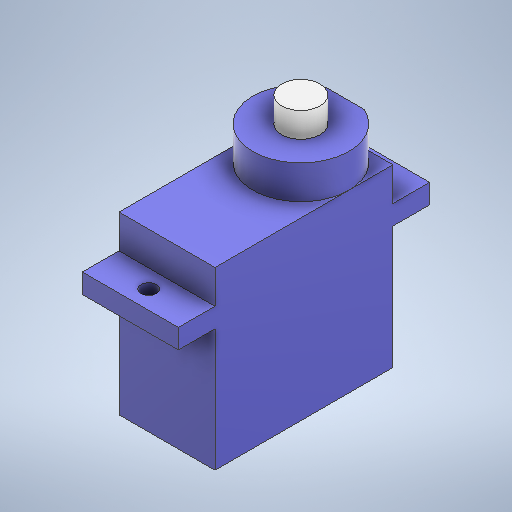
# Autodesk Inventor part: SG90
Saved by Autodesk Inventor 2025.3 (Build 293356030, 356C)
## iProperties
Created: 2025-10-27
Part Number: SG90
Material: 폴리스티렌
Document SubType Name: Modeling
Designer: work
Density: 1.021 g/cm^3
Appearance: 매끄러움 - 흰색
Author: work
Autodesk Inventor part; units mm, degrees
ref_plane "YZ Plane" through (0, 0, 0) normal (1, 0, 0) x (0, 1, 0)
ref_plane "XZ Plane" through (0, 0, 0) normal (0, 1, 0) x (-1, 0, 0)
sketch "스케치1" plane through (0, 0, 0) normal (0, 1, 0) x (-1, 0, 0)
  line L0 (0, 0) -> (12.3, 0)
  line L1 (12.3, 0) -> (12.3, -22.8)
  line L2 (12.3, -22.8) -> (0, -22.8)
  line L3 (0, -22.8) -> (0, 0)
  dimension "d0" = 12.3
  dimension "d1" = 22.8
  constraints: 8 end point, 2 parallel, 1 horizontal, 1 perpendicular
  measures "d0" distance of L1.end L2.end
  measures "d1" distance of L0.end L1.end
extrude "돌출1" add sketch "스케치1" along normal blind 22.5
ref_plane "작업 평면1" through (0, 18.2, 0) normal (0, -1, 0) x (1, 0, 0)
sketch "스케치2" plane through (0, 18.2, 0) normal (0, -1, 0) x (1, 0, 0)
  line L0 (-12.3, 4.7) -> (0, 4.7)
  line L1 (0, 4.7) -> (0, -27.5)
  line L2 (0, -27.5) -> (-12.3, -27.5)
  line L3 (-12.3, -27.5) -> (-12.3, 4.7)
  line L4 (0, -22.8) -> (-12.3, -22.8) projected
  line L5 (-12.3, -22.8) -> (-12.3, 0) projected
  line L6 (-12.3, 0) -> (0, 0) projected
  line L7 (0, 0) -> (0, -22.8) projected
  line L8 (0, 0) -> (0, -22.8) projected
  line L9 (-12.3, -22.8) -> (-12.3, 0) projected
  line L10 (-6.15, 4.7) -> (-6.15, 0) construction
  line L11 (-12.3, 0) -> (0, 0) projected
  line L12 (-6.15, -27.5) -> (-6.15, -22.8) construction
  circle A0 centre (-6.15, 2.35) radius 1
  circle A1 centre (-6.15, -25.15) radius 1
  point P0 (0, -11.4)
  point P1 (-12.3, -11.4)
  dimension "d5" = 32.2
  dimension "d6" = 2
  dimension "d7" = 2
  constraints: 12 end point, 10 midpoint, 2 centre point, 2 parallel, 1 horizontal, 1 perpendicular
  measures "d5" distance between parallel lines of L2 L0
  measures "d6" diameter of A0
  measures "d7" diameter of A1
extrude "돌출2" add sketch "스케치2" along normal blind 2.5 contours L0 L1 L6 L3 | L4 L1 L2 L3
sketch "스케치3" plane through (0, 22.5, 0) normal (0, 1, 0) x (1, 0, 0)
  circle A0 centre (-6.15, 17.15) radius 6.15
  line L0 (-12.3, 22.8) -> (-12.3, 0) projected
  line L1 (0, 0) -> (0, 22.8) projected
  line L2 (0, 27.5) -> (0, 22.8) projected
  line L3 (-12.3, 27.5) -> (0, 27.5) projected
  line L4 (-12.3, 22.8) -> (-12.3, 27.5) projected
  line L5 (0, 22.8) -> (-12.3, 22.8) projected
  circle A1 centre (-6.15, 25.15) radius 1 projected
  point P0 (-3.721, 22.8)
  point P1 (-8.579, 22.8)
  dimension "d10" = 8
  constraints: 2 tangent, 1 centre point
  measures "d10" distance of A1.centre A0.centre
extrude "돌출3" add sketch "스케치3" along normal blind 4.3 contours A0 L5 picked at (-4.8605, 15.0815)
sketch "스케치4" plane through (0, 26.8, 0) normal (0, 1, 0) x (1, 0, 0)
  arc A0 (-8.579, 22.8) -> (-3.721, 22.8) centre (-6.15, 17.15) ccw projected
  line L0 (-3.721, 22.8) -> (-8.579, 22.8) projected
  circle A1 centre (-6.15, 17.15) radius 2.45
  point P0 (0, 0)
  dimension "d13" = 4.9
  constraints: 1 centre point, 1 coincident
  measures "d13" diameter of A1
extrude "돌출4" add sketch "스케치4" along normal blind 3.2 contours A1
